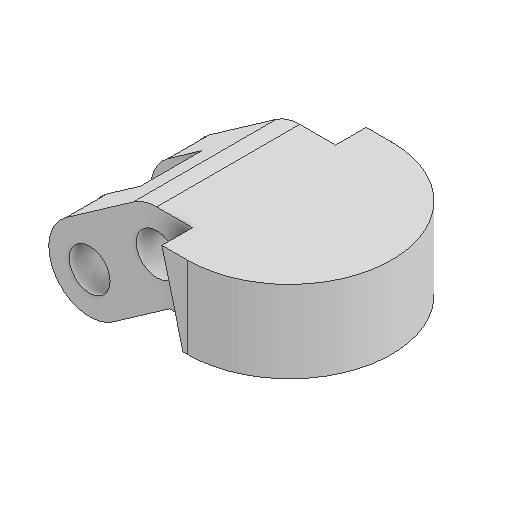
# Autodesk Inventor part: bar_bc
Saved by Autodesk Inventor 2026.1 (Build 301233020, 233B)
## iProperties
Created: 2025-11-26
Part Number: bar_bc
Material: Generic
Document SubType Name: Modeling
Designer: ferul
Density: 1 g/cm^3
Appearance: Default
Author: ferul
Autodesk Inventor part; units mm, degrees
ref_plane "YZ Plane" through (0, 0, 0) normal (1, 0, 0) x (0, 1, 0)
ref_plane "XZ Plane" through (0, 0, 0) normal (0, 1, 0) x (-1, 0, 0)
ref_plane "XY Plane" through (0, 0, 0) normal (0, 0, 1) x (1, 0, 0)
sketch "Sketch1" plane through (0, 0, 0) normal (0, 0, 1) x (1, 0, 0)
  circle A0 centre (-6.8115, 0) radius 5
  line L0 (-6.8115, 0) -> (9.5883, 11.4999) construction
  line L1 (-1.0702, -8.1876) -> (15.3297, 3.3122)
  line L2 (3.847, 19.6875) -> (-12.5528, 8.1876)
  arc A1 (-12.5528, 8.1876) -> (-1.0702, -8.1876) centre (-6.8115, 0) ccw
  arc A2 (15.3297, 3.3122) -> (3.847, 19.6875) centre (9.5883, 11.4999) ccw
  line L3 (48.5, 24) -> (48.5, 24)
  line L4 (48.5, 24) -> (48.5, 6) construction
  line L5 (48.5, 6) -> (48.5, 6)
  line L6 (48.5, 6) -> (48.5, 24) construction
  line L7 (49.5883, 1.4999) -> (49.5883, 21.4999)
  line L8 (49.5883, 21.4999) -> (9.5883, 21.4999)
  line L9 (49.5883, 1.4999) -> (12.7451, 1.4999)
  line L10 (-6.8115, 0) -> (45.0405, 0) construction
  circle A3 centre (9.5883, 11.4999) radius 5
  point P0 (0, 0)
  point P1 (1.3884, 5.7499)
  dimension "d_hole" = 10
  dimension "d6" = 20
  dimension "theta_3" = 35.039
  dimension "d16" = 90
  dimension "d17" = 20
  dimension "l_b" = 20.03
  dimension "d19" = 10
  dimension "d20" = 40
  constraints: 24 end point, 5 point on circle, 5 tangent, 4 centre point, 3 horizontal, 2 parallel, 1 coincident, 1 midpoint, 1 point on line, 1 other
  measures "d_hole" diameter of A0
  measures "d6" diameter of A2
  measures "theta_3" angle of L10 L0
  measures "d16" angle of L10 L7
  measures "d17" distance of L7.start L7.end
  measures "l_b" distance of L0.end L0.start
  measures "d19" diameter of A3
  measures "d20" distance from line of L7 L0.end
extrude "Extrusion1" add sketch "Sketch1" along normal mid plane 50
fillet "Fillet1" radius 25 2 edges at (49.5883, 11.4999, 25) (49.5883, 11.4999, -25)
sketch "Sketch2" plane through (0, 0, 25) normal (0, 0, 1) x (1, 0, 0)
  line L0 (24.5883, 21.4999) -> (24.5883, 1.4999) projected
  line L1 (24.5883, 21.4999) -> (9.5883, 21.4999) projected
  line L2 (24.5883, 1.4999) -> (48.0857, 1.4999) construction
  circle A0 centre (-6.8115, 0) radius 5 projected
  arc A1 (9.5883, 21.4999) -> (3.847, 19.6875) centre (9.5883, 11.4999) ccw projected
  line L3 (3.847, 19.6875) -> (-12.5528, 8.1876) projected
  arc A2 (-12.5528, 8.1876) -> (-1.0702, -8.1876) centre (-6.8115, 0) ccw projected
  line L4 (-1.0702, -8.1876) -> (12.7451, 1.4999) projected
  circle A3 centre (9.5883, 11.4999) radius 5 projected
  circle A4 centre (9.5883, 11.4999) radius 10
  line L5 (12.7451, 1.4999) -> (24.5883, 1.4999) projected
  line L6 (-1.7102, 1.4999) -> (-209.2293, 1.4999)
  line L7 (24.5883, 21.4999) -> (24.5883, 1.4999) projected
  line L8 (24.5883, 21.4999) -> (9.5883, 21.4999) projected
  line L9 (12.7451, 1.4999) -> (24.5883, 1.4999) projected
  line L10 (18.3681, 21.4999) -> (23.5293, 1.4999)
  point P0 (0, 0)
  point P1 (42.9703, 3.1304)
  point P2 (9.5883, 21.4999)
  point P3 (26.8619, 21.1461)
  point P4 (12.7451, 1.4999)
  point P5 (23.5293, 1.4999)
  point P6 (18.3681, 21.4999)
  dimension "w_cd" = 20
  dimension "theta_4" = 104.47
  dimension "d27" = 11
  constraints: 6 end point, 2 point on line, 1 centre point, 1 coincident, 1 horizontal, 1 tangent, 2 other
  measures "w_cd" diameter of A4
  measures "theta_4" angle to the sketch x axis of L10
  measures "d27" distance from line of A4.centre L10
extrude "Extrusion2" cut sketch "Sketch2" against normal blind 7.5 contours L10 L5 L4 A2 L3 A4 L1 | A4 A1 | A0 L6 | L6 A0 | A3
mirror "Mirror1" about plane through (0, 0, 0) normal (0, 0, 1) of "Extrusion2"
sketch "Sketch3" plane through (0, 0, 0) normal (0, 0, 1) x (1, 0, 0)
  circle A0 centre (9.5883, 11.4999) radius 5 projected
  arc A1 (9.5883, 21.4999) -> (3.847, 19.6875) centre (9.5883, 11.4999) ccw projected
  line L0 (-12.5528, 8.1876) -> (3.847, 19.6875) projected
  arc A2 (-12.5528, 8.1876) -> (-1.0702, -8.1876) centre (-6.8115, 0) ccw projected
  line L1 (12.7451, 1.4999) -> (-1.0702, -8.1876) projected
  circle A3 centre (-6.8115, 0) radius 5 projected
  line L2 (-6.8115, 0) -> (9.5883, 11.4999) construction
  line L3 (1.3884, 5.7499) -> (7.1298, -2.4377)
  line L4 (1.3884, 5.7499) -> (-4.3529, 13.9376)
  line L5 (23.5293, 1.4999) -> (12.7451, 1.4999) projected
  line L6 (9.5883, 21.4999) -> (18.3681, 21.4999) projected
  line L7 (18.3681, 21.4999) -> (23.5293, 1.4999) projected
  point P0 (0, 0)
  constraints: 6 end point, 2 midpoint, 1 perpendicular, 1 point on line
extrude "Extrusion3" cut sketch "Sketch3" along normal mid plane 15 contours L4 L3 L1 A2 L0
equation "\"d6\" = w_cd"
equation "\"d17\" = d6"
equation "\"d19\" = d_hole"
equation "\"d9\" = 0.5 * d7"
equation "\"d7\" = 50"
body "Solid1"
